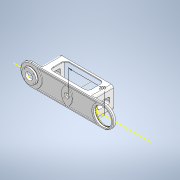
# Autodesk Inventor part: 1.2_1_SideArm
Saved by Autodesk Inventor 2021 (Build 250183000, 183)
## iProperties
Created: 2025-11-12
Part Number: 1.2_1_SideArm
Material: ABS Plastic
Document SubType Name: Modeling
Designer: Admin
Density: 1.06 g/cm^3
Appearance: Smooth - White
Mass: 1137.96 g
Surface Area: 1903.2 cm^2
Volume: 1073.55 cm^3
Author: Admin
Autodesk Inventor part; units mm, degrees
ref_plane "YZ Plane" through (0, 0, 0) normal (1, 0, 0) x (0, 1, 0)
ref_plane "XZ Plane" through (0, 0, 0) normal (0, 1, 0) x (-1, 0, 0)
ref_plane "XY Plane" through (0, 0, 0) normal (0, 0, 1) x (1, 0, 0)
sketch "Sketch1" plane through (0, 0, 0) normal (0, 0, 1) x (1, 0, 0)
  line L0 (0, 0) -> (400, 0) construction
  line L1 (0, -60) -> (400, -60)
  line L2 (400, 60) -> (0, 60)
  arc A0 (0, 60) -> (0, -60) centre (0, 0) ccw
  arc A1 (400, -60) -> (400, 60) centre (400, 0) ccw
  point P0 (200, 0)
  dimension "d0" = 400
  dimension "d1" = 60
  constraints: 8 end point, 4 point on circle, 4 tangent, 2 centre point, 1 horizontal, 1 midpoint, 1 parallel
  measures "d0" distance of L0.start L0.end
  measures "d1" radius of A0
extrude "Extrusion1" add sketch "Sketch1" along normal blind 11
sketch "Sketch2" plane through (0, 0, 0) normal (0, 1, 0) x (-1, 0, 0)
  line L0 (-400, 11) -> (0, 11) projected
  line L1 (0, 11) -> (0, 22)
  line L2 (0, 22) -> (-40, 22)
  line L3 (-40, 22) -> (-40, 12)
  line L4 (-40, 12) -> (-41, 12)
  line L5 (-41, 12) -> (-41, 11)
  point P0 (0, 0)
  dimension "d4" = 11
  dimension "d5" = 1
  dimension "d6" = 1
  dimension "d7" = 40
  constraints: 10 end point, 4 perpendicular, 1 point on line, 1 vertical
  measures "d4" distance between parallel lines of L2 L0
  measures "d5" distance of L4.end L5.end
  measures "d6" distance of L3.end L4.end
  measures "d7" distance of L1.end L2.end
revolve "Revolution1" add sketch "Sketch2" angle 360 about axis through (0, 0, 11) along (0, 0, 1)
sketch "Sketch3" plane through (0, 0, 0) normal (0, 0, -1) x (-1, 0, 0)
  line L0 (32, 32) -> (-32, 32)
  line L1 (-32, 32) -> (-32, -32)
  line L2 (-32, -32) -> (32, -32)
  line L3 (32, -32) -> (32, 32)
  line L4 (32, 32) -> (-32, -32) construction
  line L5 (-32, 32) -> (32, -32) construction
  point P0 (0, 0)
  dimension "d9" = 64
  constraints: 12 end point, 2 midpoint, 2 parallel, 2 perpendicular, 1 horizontal
  measures "d9" distance of L1.end L2.end
extrude "Extrusion2" cut sketch "Sketch3" against normal blind 5
sketch "Sketch4" plane through (0, 0, 5) normal (0, 0, -1) x (-1, 0, 0)
  point P0 (0, 0)
  point P1 (0, 0)
  constraints: 1 coincident
hole "Hole1" at (0, 0, 5) direction (0, 0, 1) diameter 40 end through all counterbore diameter 52 counterbore depth 3
sketch "Sketch5" plane through (0, 0, 5) normal (0, 0, -1) x (-1, 0, 0)
  circle A0 centre (0, 0) radius 35 construction
  line L0 (24.7487, -24.7487) -> (-24.7487, -24.7487) construction
  line L1 (-24.7487, -24.7487) -> (-24.7487, 24.7487) construction
  line L2 (-24.7487, 24.7487) -> (24.7487, 24.7487) construction
  line L3 (24.7487, 24.7487) -> (24.7487, -24.7487) construction
  line L4 (24.7487, -24.7487) -> (-24.7487, 24.7487) construction
  line L5 (-24.7487, -24.7487) -> (24.7487, 24.7487) construction
  point P0 (-24.7487, 24.7487)
  point P1 (24.7487, 24.7487)
  dimension "d19" = 70
  constraints: 12 end point, 3 coincident, 3 point on circle, 2 midpoint, 2 parallel, 2 perpendicular, 1 centre point, 1 horizontal
  measures "d19" diameter of A0
hole "Hole2" at (24.7487, -24.7487, 5) at (24.7487, 24.7487, 5) at (-24.7487, 24.7487, 5) at (-24.7487, -24.7487, 5) direction (0, 0, 1) diameter 4.5 end through all clearance for "Countersunk Flat Head Screw ISO 2009/7046" size "M4" standard "ISO"
sketch "Sketch7" plane through (0, 0, 0) normal (0, 0, 1) x (1, 0, 0)
  arc A0 (400, -60) -> (400, 60) centre (400, 0) ccw projected
  circle A1 centre (400, 0) radius 60
  point P0 (0, 0)
  constraints: 1 coincident, 3 other
extrude "Extrusion3" add sketch "Sketch7" against normal blind 3
sketch "Sketch6" plane through (0, 0, 0) normal (0, 1, 0) x (-1, 0, 0)
  line L0 (-400, -5) -> (-448, -5)
  line L1 (-448, -5) -> (-448, 1)
  line L2 (-448, 1) -> (-450, 1)
  line L3 (-450, 1) -> (-450, 11)
  line L4 (-400, 11) -> (-460, 11) projected
  line L5 (-400, 11) -> (-400, -5)
  line L6 (-672, 0) -> (112, 0) projected
  point P0 (0, 0)
  point P1 (-500, -12.1629)
  dimension "d27" = 50
  dimension "d28" = 10
  dimension "d29" = 2
  dimension "d33" = 5
  constraints: 12 end point, 2 perpendicular, 2 vertical, 1 horizontal, 1 point on line
  measures "d27" distance between parallel lines of L5 L3
  measures "d28" distance of L2.end L3.end
  measures "d29" distance of L1.end L2.end
  measures "d33" distance between parallel lines of L6 L0
revolve "Revolution2" cut sketch "Sketch6" angle 360 about axis through (400, 0, 11) along (0, 0, -1)
sketch "Sketch8" plane through (0, 0, 0) normal (0, 0, 1) x (1, 0, 0)
  line L0 (0, -60) -> (400, -60) projected
  line L1 (400, 60) -> (0, 60) projected
  line L2 (65, -60) -> (40, -60)
  line L3 (40, -60) -> (40, 60)
  line L4 (40, 60) -> (65, 60)
  line L5 (65, 60) -> (65, -60)
  line L6 (340, -60) -> (315, -60)
  line L7 (315, -60) -> (315, 60)
  line L8 (315, 60) -> (340, 60)
  line L9 (340, 60) -> (340, -60)
  line L10 (0, 84) -> (0, -84) projected
  point P0 (0, 0)
  point P1 (400, 0)
  point P2 (340, -60)
  point P3 (340, 60)
  point P4 (315, -60)
  dimension "d34" = 60
  dimension "d35" = 25
  dimension "d36" = 25
  dimension "d37" = 40
  constraints: 16 end point, 4 parallel, 4 point on line, 2 horizontal, 2 perpendicular
  measures "d34" distance from line of point (400, 0) L9
  measures "d35" distance between parallel lines of L7 L9
  measures "d36" distance between parallel lines of L3 L5
  measures "d37" distance between parallel lines of L10 L3
extrude "Extrusion4" add sketch "Sketch8" against normal blind 110 contours L3 L1 L5 L0 | L7 L1 L9 L0
sketch "Sketch9" plane through (0, 0, 0) normal (0, 0, 1) x (1, 0, 0)
  circle A0 centre (400, 0) radius 48 projected
  line L0 (-109.6, 0) -> (657.6, 0) projected
  point P0 (0, 0)
  point P1 (150, 0)
  point P2 (200, 0)
  dimension "d41" = 200
  constraints: 2 point on line
  measures "d41" distance of A0.centre point (200, 0)
fillet "Fillet1" radius 12.5 8 edges at (40, 60, -55) (65, 60, -55) (40, -60, -55) (65, -60, -55) (315, -60, -55) (340, -60, -55) (315, 60, -55) (340, 60, -55)
chamfer "Chamfer1" distance 4 angle 45 4 edges at (200, 60, 11) (-60, 0, 11) (200, -60, 11) (460, 0, 11)
sketch "Sketch10" plane through (0, 0, 0) normal (0, 1, 0) x (-1, 0, 0)
  line L0 (0, 11) -> (-400, 11) projected
  line L1 (-200, 11) -> (-200, 0)
  line L2 (-52.5, 0) -> (-327.5, 0) projected
  line L3 (-185, 0) -> (-185, 7)
  line L4 (-185, 7) -> (-186, 7)
  line L5 (-186, 7) -> (-186, 11)
  line L6 (-186, 11) -> (-186, 7)
  line L7 (-186, 11) -> (-200, 11)
  line L8 (-564, 0) -> (164, 0) projected
  line L9 (-185, 0) -> (-200, 0)
  line L10 (-200, 27) -> (-200, -8) projected
  point P0 (0, 0)
  point P1 (-186, 11)
  dimension "d46" = 15
  dimension "d47" = 1
  dimension "d48" = 7
  constraints: 14 end point, 3 perpendicular, 2 collinear, 2 point on line, 2 vertical, 1 midpoint
  measures "d46" distance between parallel lines of L1 L3
  measures "d47" distance of L3.end L4.end
  measures "d48" distance of L3.start L3.end
revolve "Revolution4" cut sketch "Sketch10" angle 360 about axis through (200, 0, 0) along (0, 0, -1)
sketch "Sketch11" plane through (0, 0, 11) normal (0, 0, 1) x (1, 0, 0)
  circle A0 centre (200, 0) radius 15 projected
  line L0 (52.5, 60) -> (327.5, 60) projected
  line L1 (52.5, 60) -> (0, 60) projected
  circle A1 centre (0, 0) radius 60
  circle A2 centre (400, 0) radius 48 projected
  arc A3 (400, 60) -> (340, 0) centre (400, 0) ccw projected
  circle A4 centre (400, 0) radius 60
  line L2 (33.1662, 50) -> (366.8338, 50)
  line L3 (40, 47.5) -> (40, -47.5) projected
  arc A5 (340, 0) -> (400, -60) centre (400, 0) ccw projected
  line L4 (33.1662, -50) -> (366.8338, -50)
  line L5 (0, -60) -> (400, -60) projected
  circle A6 centre (230, 0) radius 60
  line L6 (0, 56) -> (400, 56) projected
  circle A7 centre (170, 0) radius 60
  line L7 (-164, 0) -> (564, 0) projected
  point P0 (33.1662, 50)
  point P1 (366.8338, 50)
  point P2 (340, 0)
  point P3 (203.1662, 50)
  point P4 (203.1662, -50)
  point P5 (196.8338, -50)
  point P6 (196.8338, 50)
  dimension "d51" = 10
  dimension "d52" = 10
  dimension "d55" = 30
  dimension "d56" = 30
  constraints: 7 point on circle, 4 centre point, 2 coincident, 2 end point, 2 point on line, 2 tangent, 1 horizontal, 1 vertical, 3 other
  measures "d51" distance between parallel lines of L5 L4
  measures "d55" distance of A0.centre A7.centre
  measures "d56" distance of A0.centre A6.centre
extrude "Extrusion5" cut sketch "Sketch11" against normal blind 5 contours L7 A6 L4 A7 | A7 L2 A6 L7 | L7 A7 L2 A6 | A6 L4 A7 L7 | L7 A4 L4 A6 | A6 L2 A3 L7 | L7 A1 L2 A7 | A7 L4 A1 L7
sketch "Sketch12" plane through (0, 0, 22) normal (0, 0, 1) x (1, 0, 0)
  point P0 (0, 0)
sketch "Sketch13" plane through (0, 0, -110) normal (0, 0, -1) x (-1, 0, 0)
  line L0 (-52.5, -44.1319) -> (-52.5, 44.1319)
  line L1 (-327.5, -44.1319) -> (-327.5, 44.1319)
  line L2 (-315, -47.5) -> (-315, 47.5) projected
  line L3 (-40, -47.5) -> (-40, 47.5) projected
  line L4 (164, 0) -> (-564, 0) projected
  circle A0 centre (-400, 0) radius 50 projected
  point P0 (0, 0)
  point P1 (-52.5, 0)
  point P2 (-327.5, 0)
  point P3 (-52.5, -40)
  point P4 (-52.5, 40)
  point P5 (-327.5, 40)
  point P6 (-327.5, -40)
  dimension "d57" = 12.5
  dimension "d58" = 12.5
  dimension "d59" = 40
  dimension "d60" = 40
  dimension "d61" = 40
  dimension "d62" = 40
  constraints: 6 point on line, 4 end point, 2 midpoint, 2 vertical
  measures "d57" distance between parallel lines of L1 L2
  measures "d58" distance between parallel lines of L3 L0
  measures "d59" distance from line of L4 point (-52.5, -40)
  measures "d60" distance from line of L4 point (-327.5, -40)
  measures "d61" distance from line of L4 point (-327.5, 40)
  measures "d62" distance from line of L4 point (-52.5, 40)
hole "Hole3" at (327.5, -40, -110) at (327.5, 40, -110) at (52.5, 40, -110) at (52.5, -40, -110) direction (0, 0, 1) diameter 8 depth 15 tip angle 118
fillet "Fillet2" radius 0.5 1 edges at (350, 0, 1)
fillet "Fillet3" radius 0.5 1 edges at (-40, 0, 12)
fillet "Fillet4" radius 0.2 1 edges at (215, 0, 7)
sketch "Sketch14" plane through (0, 0, 0) normal (1, 0, 0) x (0, 1, 0)
  point P0 (0, 0)
sketch "Sketch15" plane through (0, 0, 0) normal (0, 0, -1) x (-1, 0, 0)
  arc A0 (-315, 47.5) -> (-327.5, 60) centre (-327.5, 47.5) ccw projected
  line L0 (-327.5, 60) -> (-315, 47.5)
  arc A1 (-52.5, 60) -> (-65, 47.5) centre (-52.5, 47.5) ccw projected
  line L1 (-65, 47.5) -> (-52.5, 60)
  line L2 (-52.5, 60) -> (-327.5, 60) projected
  line L3 (-315, 47.5) -> (-315, -47.5) projected
  line L4 (-315, 47.5) -> (-65, 47.5) construction
  line L5 (-190, 47.5) -> (-190, 1016.2838) construction
  line L6 (-327.5, 60) -> (-52.5, 60)
  line L7 (-315, 47.5) -> (-315, 55)
  line L8 (-315, 55) -> (-65, 55)
  line L9 (-65, 55) -> (-65, 47.5)
  point P0 (0, 0)
  dimension "d75" = 5
  constraints: 16 end point, 2 vertical, 1 horizontal, 1 midpoint, 1 parallel, 1 perpendicular, 1 tangent
  measures "d75" distance between parallel lines of L2 L8
extrude "Extrusion6" add sketch "Sketch15" along normal up to surface (110 mm away) contours A0 L2 A1 L9 L8 L7
mirror "Mirror1" about plane through (0, 0, 0) normal (0, 1, 0) of "Extrusion6"
sketch "Sketch16" plane through (52.5, 60, -110) normal (0, 1, 0) x (1, 0, 0)
  line L0 (30, -10) -> (245, -10)
  line L1 (245, -10) -> (245, -100)
  line L2 (245, -100) -> (30, -100)
  line L3 (30, -100) -> (30, -10)
  line L4 (275, 0) -> (0, 0) projected
  line L5 (0, -110) -> (-52.5, -110) projected
  line L6 (0, -110) -> (0, 0) projected
  line L7 (275, -110) -> (275, 0) projected
  dimension "d78" = 10
  dimension "d79" = 10
  dimension "d80" = 30
  dimension "d81" = 30
  constraints: 8 end point, 2 parallel, 1 horizontal, 1 perpendicular
  measures "d78" distance between parallel lines of L4 L0
  measures "d79" distance between parallel lines of L2 L5
  measures "d80" distance between parallel lines of L3 L6
  measures "d81" distance between parallel lines of L7 L1
extrude "Extrusion7" cut sketch "Sketch16" against normal through all
fillet "Fillet5" radius 20 8 edges at (82.5, 57.5, -10) (82.5, 57.5, -100) (297.5, 57.5, -10) (297.5, 57.5, -100) (82.5, -57.5, -100) (82.5, -57.5, -10) (297.5, -57.5, -10) (297.5, -57.5, -100)
sketch "Sketch17" plane through (40, -47.5, 0) normal (-1, 0, 0) x (0, 0, 1)
  line L0 (-90, 65) -> (-20, 65)
  line L1 (-20, 65) -> (-20, 30)
  line L2 (-20, 30) -> (-90, 30)
  line L3 (-90, 30) -> (-90, 65)
  line L4 (-110, 95) -> (0, 95) projected
  line L5 (0, 0) -> (-110, 0) projected
  line L6 (0, -12.5) -> (0, 107.5) projected
  line L7 (-110, 0) -> (-110, 95) projected
  point P0 (0, 47.5)
  dimension "d85" = 30
  dimension "d86" = 30
  dimension "d87" = 20
  dimension "d88" = 20
  constraints: 8 end point, 2 parallel, 1 horizontal, 1 perpendicular
  measures "d85" distance between parallel lines of L4 L0
  measures "d86" distance between parallel lines of L5 L2
  measures "d87" distance between parallel lines of L6 L1
  measures "d88" distance between parallel lines of L3 L7
extrude "Extrusion8" cut sketch "Sketch17" against normal through all contours L0 L1 L2 L3
fillet "Fillet6" radius 10 8 edges at (327.5, 17.5, -20) (327.5, -17.5, -20) (327.5, -17.5, -90) (327.5, 17.5, -90) (52.5, 17.5, -20) (52.5, -17.5, -20) (52.5, 17.5, -90) (52.5, -17.5, -90)
fillet "Fillet7" radius 5 4 edges at (65, 55, -55) (65, -55, -55) (315, 55, -55) (315, -55, -55)
fillet "Fillet8" radius 10 8 edges at (33.1662, -50, 8.5) (33.1662, 50, 8.5) (196.8338, 50, 8.5) (203.1662, 50, 8.5) (203.1662, -50, 8.5) (196.8338, -50, 8.5) (366.8338, -50, 8.5) (366.8338, 50, 8.5)
chamfer "Chamfer2" distance 1 angle 45 3 edges at (214, 0, 11) (215, 0, 0) (350, 0, 11)
fillet "Fillet9" radius 4 32 edges at (340, 14.5711, -22.9289) (340, 17.5, -55) (340, 14.5711, -87.0711) (340, 0, -90) (340, -14.5711, -87.0711) (340, -17.5, -55) (340, -14.5711, -22.9289) (340, 0, -20) (315, -14.5711, -22.9289) (315, -17.5, -55) (315, -14.5711, -87.0711) (315, 0, -90) (315, 14.5711, -87.0711) (315, 17.5, -55) (315, 14.5711, -22.9289) (315, 0, -20) (40, 0, -90) (40, -14.5711, -87.0711) (40, -17.5, -55) (40, -14.5711, -22.9289) (40, 0, -20) (40, 14.5711, -22.9289) (40, 17.5, -55) (40, 14.5711, -87.0711) (65, 14.5711, -22.9289) (65, 17.5, -55) (65, 14.5711, -87.0711) (65, 0, -90) (65, -14.5711, -87.0711) (65, -17.5, -55) (65, -14.5711, -22.9289) (65, 0, -20)
equation "\"d60\" = d59"
equation "\"d61\" = d59"
equation "\"d62\" = d59"
equation "\"d88\" = d87"
body "Solid1"
